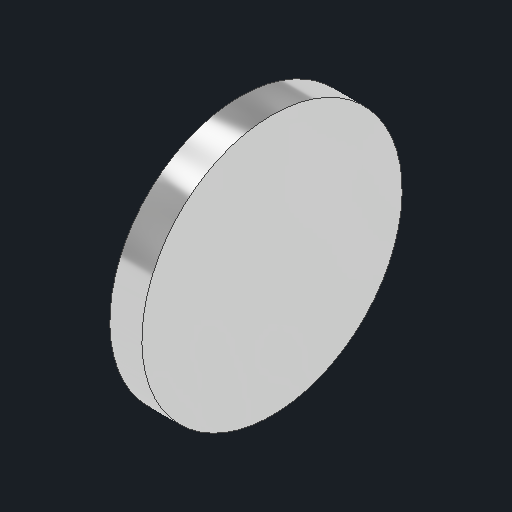
# Autodesk Inventor part: c8n_primary_mirror
Saved by Autodesk Inventor 2027.1 (Build 311270010, 270A)
## iProperties
Created: 2026-11-04
Part Number: c8n_primary_mirror
Material: Generic
Description: Primary mirror 203 mm, 1000 mm focal length
Document SubType Name: Modeling
Designer: Claude (from photos)
Density: 1 g/cm^3
Appearance: Mirror
Author: alexg
Autodesk Inventor part; units mm, degrees
ref_plane "XZ Plane" through (0, 0, 0) normal (0, 1, 0) x (-1, 0, 0)
ref_plane "XY Plane" through (0, 0, 0) normal (0, 0, 1) x (1, 0, 0)
ref_plane "Work Plane1" through (18, 0, 0) normal (1, 0, 0) x (0, 1, 0)
sketch "Primary 203 mm f/5 sketch" plane through (18, 0, 0) normal (1, 0, 0) x (0, 1, 0)
  circle A0 centre (0, 0) radius 101.5
  constraints: 1 centre point
extrude "Primary 203 mm f/5" add sketch "Primary 203 mm f/5 sketch" along normal blind 25
body "Solid1"
